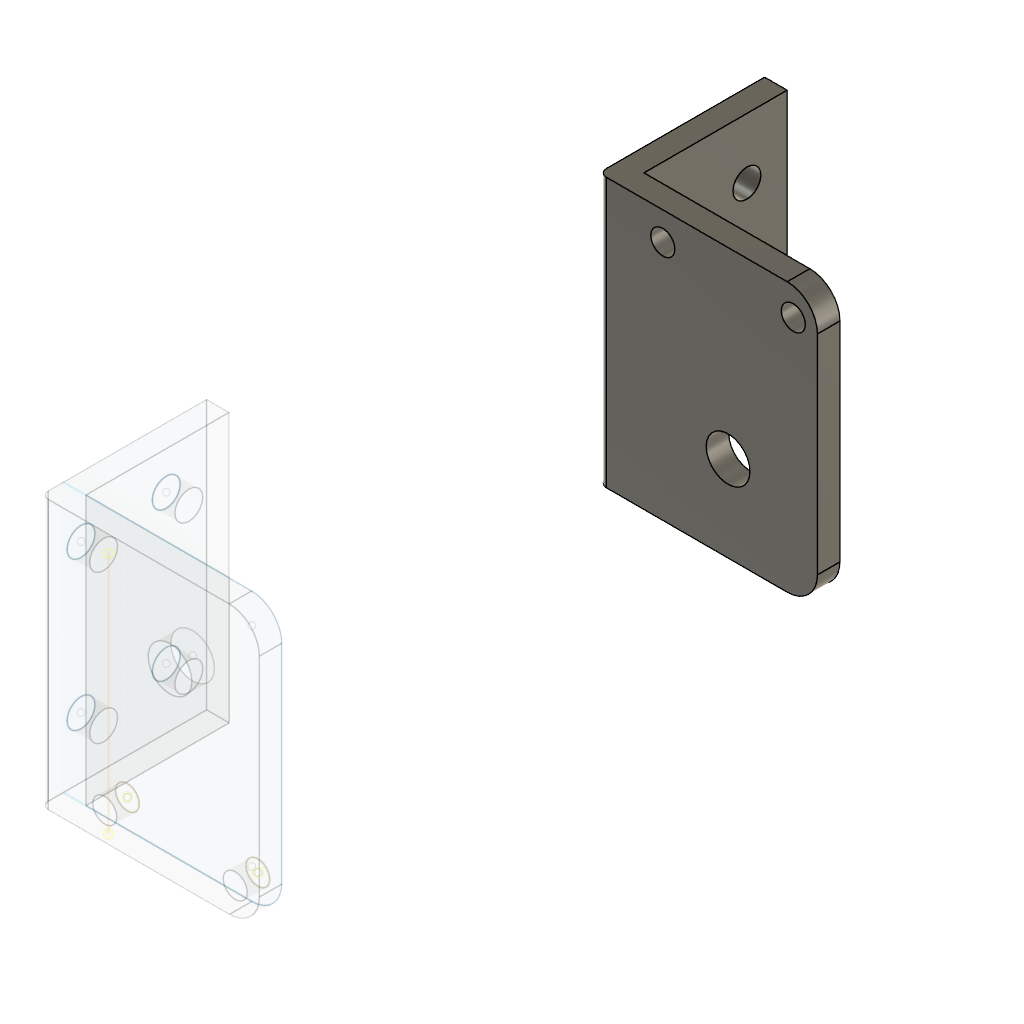
机械车01 (Autodesk Fusion 360 archive; units mm, degrees)
design "motor"
description: STEP AP214
part number: motor
part number: 2026-10-07-12-05-36-152
part number: 2026-10-07-14-24-25-722
Autodesk Fusion 360 part; units mm, degrees
sketch "草图2" plane through (0, -9.65, 0) normal (0, -1, 0) x (1, 0, 0) in component "Component"
  line L0 (-1.9666, 18.47) -> (1.9666, 18.47)
  arc A0 (1.9666, 18.47) -> (-1.9666, 18.47) centre (0, 16.62) ccw
  line L1 (-17.15, 28) -> (7.85, 28)
  line L2 (11.85, 24) -> (11.85, -3.6667)
  line L3 (7.85, -7.6667) -> (-17.15, -7.6667)
  line L4 (-17.15, -7.6667) -> (-17.15, 28)
  circle A1 centre (0, 16.62) radius 2.9
  circle A2 centre (-8.65, -3.95) radius 1.5
  circle A3 centre (8.65, -3.95) radius 1.5
  circle A4 centre (-8.65, -3.95) radius 1.6
  circle A5 centre (8.65, -3.95) radius 1.6
  line L5 (-14.15, 28) -> (-14.15, -7.6667)
  line L6 (-11.15, 22.8) -> (-11.15, -9.4)
  arc A6 (11.85, 24) -> (7.85, 28) centre (7.85, 24) ccw
  arc A7 (7.85, -7.6667) -> (11.85, -3.6667) centre (7.85, -3.6667) ccw
  dimension "d47" = 5.8
  dimension "d48" = 3.2
  dimension "d49" = 3.2
  dimension "d50" = 3
  dimension "d51" = 3
  dimension "d52" = 4
  dimension "d53" = 4
  constraint horizontal L1
  constraint perpendicular L1 L2
  constraint perpendicular L1 L4
  constraint horizontal L3
  constraint concentric A0 A1
  constraint concentric A2 A4
  constraint concentric A3 A5
  constraint coincident L1 L5.start
  constraint coincident L3 L5.end
  constraint perpendicular L3 L5
  constraint tangent L1 A6
  constraint tangent L2 A6
  constraint tangent L2 A7
  constraint tangent L3 A7
  measures "d47" diameter of A1
  measures "d48" diameter of A4
  measures "d49" diameter of A5
  measures "d50" distance of L5 L6
  measures "d51" distance of L4 L5
  measures "d52" radius of A6
  measures "d53" radius of A7
extrude "拉伸4" add sketch "草图2" along normal blind 3 contours L1 L3 L4 L5 | L1 L2 L3 L5 A6 A7 makes body 1 in component "Component"
extrude "拉伸5" add sketch "草图2" against normal blind 19 contours L1 L3 L4 L5 bodies 1 in component "Component"
sketch "草图3" plane through (-17.15, 0, 0) normal (-1, 0, 0) x (0, -1, 0) in component "Component"
  line L0 (-9.35, -7.6667) -> (12.65, -7.6667)
  line L1 (12.65, -7.6667) -> (12.65, 28)
  line L2 (12.65, 28) -> (-9.35, 28)
  line L3 (-9.35, 28) -> (-9.35, -7.6667)
  line L4 (1.65, 28) -> (1.65, -7.6667) construction
  line L5 (-9.35, 10.1667) -> (12.65, 10.1667) construction
  circle A0 centre (-4, 20) radius 1.85
  circle A1 centre (7.3, 20) radius 1.85
  circle A2 centre (-4, 0.3333) radius 1.85
  circle A3 centre (7.3, 0.3333) radius 1.85
  dimension "d58" = 3.7
  constraint midpoint L2 L4.start
  constraint midpoint L0 L4.end
  constraint midpoint L3 L5.start
  constraint midpoint L1 L5.end
  constraint symmetric L4 A0 A1
  constraint symmetric L5 A0 A2
  constraint symmetric L5 A1 A3
  measures "d58" diameter of A0
extrude "拉伸6" cut sketch "草图3" against normal blind 3 contours A0 | A1 | A2 | A3 bodies 1 in component "Component"
fillet "圆角4" radius 1 1 edges at (-17.15, -12.65, 10.1667) on bodies 1 in component "Component"
sketch "草图1" plane through (0, -9.65, 0) normal (0, -1, 0) x (1, 0, 0) in component "支座2"
  line L0 (-14.15, -7.6667) -> (-14.15, 28)
  line L1 (-14.15, 28) -> (7.85, 28)
  arc A0 (11.85, 24) -> (7.85, 28) centre (7.85, 24) ccw
  line L2 (11.85, 24) -> (11.85, -3.6667)
  arc A1 (7.85, -7.6667) -> (11.85, -3.6667) centre (7.85, -3.6667) ccw
  line L3 (7.85, -7.6667) -> (-14.15, -7.6667)
  circle A2 centre (8.65, -3.95) radius 1.6
  circle A3 centre (0, 16.62) radius 2.9
  circle A4 centre (-8.65, -3.95) radius 1.6
  line L4 (-17.15, 28) -> (-14.15, 28)
  line L5 (-14.15, 28) -> (-14.15, -7.6667)
  line L6 (-14.15, -7.6667) -> (-17.15, -7.6667)
  line L7 (-17.15, -7.6667) -> (-17.15, 28)
  line L8 (-17.15, -7.6667) -> (7.85, -7.6667)
  arc A5 (7.85, -7.6667) -> (11.85, -3.6667) centre (7.85, -3.6667) ccw
  line L9 (11.85, 24) -> (11.85, -3.6667)
  arc A6 (11.85, 24) -> (7.85, 28) centre (7.85, 24) ccw
  line L10 (7.85, 28) -> (-14.15, 28)
  line L11 (-14.15, 28) -> (-14.15, -7.6667)
  line L12 (-17.15, 28) -> (-17.15, -7.6667)
  line L13 (-14.15, -7.6667) -> (7.85, -7.6667)
  line L14 (-14.15, 28) -> (-17.15, 28)
  line L15 (11.85, 24) -> (11.85, 28) construction
  line L16 (11.85, 28) -> (7.85, 28) construction
  line L17 (7.85, -7.6667) -> (11.85, -7.6667) construction
  line L18 (11.85, -7.6667) -> (11.85, -3.6667) construction
  line L19 (11.85, 28) -> (-14.15, -7.6667) construction
  line L20 (11.85, -7.6667) -> (-14.15, 28) construction
  line L21 (11.85, 10.1667) -> (-14.15, 10.1667) construction
  circle A7 centre (0, 3.7133) radius 2.9
  circle A8 centre (-8.65, 24.2833) radius 1.6
  circle A9 centre (8.65, 24.2833) radius 1.6
  line L22 (-14.15, -7.6667, 0) -> (-14.15, -7.6667, -19)
  line L23 (-14.15, -7.6667, -19) -> (-17.15, -7.6667, -19)
  line L24 (-17.15, -7.6667, -19) -> (-17.15, -7.6667, 0)
  line L25 (-14.15, 28, -19) -> (-14.15, 28, 0)
  line L26 (-14.15, -7.6667, -19) -> (-14.15, 28, -19)
  point P0 (11.85, -3.6667)
  point P1 (-14.15, -7.6667)
  point P2 (-17.15, -7.6667)
  point P3 (-17.15, -7.6667)
  point P4 (-14.15, 28)
  constraint coincident P3 P2
  constraint coincident A1.start L3.start
  constraint coincident P0 L2.end
  constraint tangent L3 A5
  constraint coincident A0.start L2.start
  constraint tangent A5 L9
  constraint coincident L1.end A0.end
  constraint tangent L9 A6
  constraint coincident P4 L0.end
  constraint coincident P1 L0.start
  constraint coincident L4.start L7.end
  constraint tangent A0 L15
  constraint tangent A6 L16
  constraint tangent A1 L17
  constraint tangent A1 L18
  constraint midpoint L2 L21.start
  constraint midpoint L5 L21.end
  constraint symmetric A2 L21 A9
  constraint symmetric A3 L21 A7
  constraint symmetric A4 L21 A8
  constraint coincident L0.start L3.end
extrude "拉伸1" add sketch "草图1" along normal blind 3 separate body contours L0 L4 L5 L6 L7 L8 L11 L12 L14 | L0 L1 A0 L2 A1 L3 L5 L8 A5 L9 A6 L10 L11 L13 | A2 | A3 | A4 makes body 2 in component "支座2"
sketch "草图2 (2)" plane through (-14.15, 0, 0) normal (1, 0, 0) x (0, 1, 0) in component "支座2"
  circle A0 centre (-7.3, 20) radius 1.85
  circle A1 centre (-7.3, 0.3333) radius 1.85
  circle A2 centre (4, 20) radius 1.85
  circle A3 centre (4, 0.3333) radius 1.85
  line L0 (-9.65, 28) -> (-9.65, -7.6667)
  line L1 (-9.65, -7.6667) -> (9.35, -7.6667)
  line L2 (9.35, -7.6667) -> (9.35, 28)
  line L3 (9.35, 28) -> (-9.65, 28)
  circle A4 centre (4, 0.3333) radius 1.85
  circle A5 centre (-7.3, 0.3333) radius 1.85
  circle A6 centre (4, 20) radius 1.85
  circle A7 centre (-7.3, 20) radius 1.85
  constraint concentric A3 A4
  constraint concentric A1 A5
  constraint concentric A2 A6
  constraint concentric A0 A7
extrude "拉伸2" add sketch "草图2 (2)" against normal blind 3 bodies 2 in component "支座2"
fillet "圆角1" radius 1 1 edges at (-17.15, -12.65, 10.1667) on bodies 2 in component "支座2"
fillet "圆角2" [rolled back] radius 1 in component "Component"
fillet "圆角3" [rolled back] radius 1 in component "Component"
sketch "草图1 (2)" plane through (0, -17.65, 0) normal (0, -1, 0) x (1, 0, 0) in component "Component"
  arc A0 (1.9666, 14.77) -> (1.9666, 18.47) centre (0, 16.62) ccw
  line L0 (1.9666, 18.47) -> (-1.9666, 18.47)
  arc A1 (-1.9666, 18.47) -> (-1.9666, 14.77) centre (0, 16.62) ccw
  line L1 (-1.9666, 14.77) -> (1.9666, 14.77)
  circle A2 centre (0, 16.62) radius 0.95
  line L2 (-14.65, 26.8492) -> (-14.65, -8.725)
  line L3 (-14.65, -8.725) -> (11.8937, -8.725)
  line L4 (11.8937, -8.725) -> (11.8937, 26.8492)
  line L5 (5.8937, 32.8492) -> (-8.65, 32.8492)
  line L6 (-11.65, 32.8492) -> (-11.65, -8.725)
  line L7 (-11.15, 22.8) -> (-11.15, -9.4)
  arc A3 (-8.65, 32.8492) -> (-14.65, 26.8492) centre (-8.65, 26.8492) ccw
  arc A4 (11.8937, 26.8492) -> (5.8937, 32.8492) centre (5.8937, 26.8492) ccw
  circle A5 centre (-8.65, -3.95) radius 1.5
  circle A6 centre (8.65, -3.95) radius 1.5
  circle A7 centre (0, 30.3) radius 1.25
  circle A8 centre (0, 16.62) radius 2.8
  circle A9 centre (-8.65, -3.95) radius 1.6
  circle A10 centre (8.65, -3.95) radius 1.6
  dimension "d33" = 0.5
  dimension "d34" = 3
  dimension "d35" = 6
  dimension "d36" = 5.6
  dimension "d37" = 3.2
  dimension "d38" = 3.2
  constraint vertical L2
  constraint perpendicular L2 L3
  constraint perpendicular L3 L4
  constraint perpendicular L2 L5
  constraint coincident L5 L6.start
  constraint coincident L3 L6.end
  constraint perpendicular L3 L6
  constraint tangent L2 A3
  constraint tangent L5 A3
  constraint tangent L4 A4
  constraint tangent L5 A4
  constraint equal A3 A4
  constraint concentric A0 A8
  constraint concentric A5 A9
  constraint concentric A6 A10
  measures "d33" distance of L6 L7
  measures "d34" distance of L2 L6
  measures "d35" radius of A3
  measures "d36" diameter of A8
  measures "d37" diameter of A9
  measures "d38" diameter of A10
extrude "拉伸1'" [suppressed] in component "Component"
extrude "拉伸2'" [suppressed] in component "Component"
extrude "拉伸3" [suppressed] in component "Component"
fillet "圆角1'" [suppressed] in component "Component"
extrude "拉伸1''" [suppressed]
sketch "草图2 (3)" plane through (-11.15, 0, 0) normal (-1, 0, 0) x (0, -1, 0)
  line L0 (8.55, 27.8) -> (8.55, -9.4)
  line L1 (8.55, -9.4) -> (11.55, -9.4)
  line L2 (11.55, -9.4) -> (11.55, 27.8)
  line L3 (11.55, 27.8) -> (8.55, 27.8)
  line L4 (8.55, 27.8) -> (-10.4031, 27.8)
  line L5 (-10.4031, 27.8) -> (-10.4031, -9.3431)
  line L6 (-10.4031, -9.3431) -> (8.55, -9.4)
  constraint coincident L0.start L3.end
  constraint perpendicular L0 L4
  constraint perpendicular L4 L5
  constraint coincident L0.end L1.start
extrude "拉伸2''" [suppressed]
extrude "拉伸3'" [suppressed]
fillet "圆角1''" [suppressed]
extrude "拉伸4'" [suppressed]
component "Component" placed x (1, 0, 0) y (0, 1, 0) z (0, 0, 1) at (0, 0, 0)
component "支座2" placed x (1, 0, 0) y (0, 1, 0) z (0, 0, 1) at (0, 0, 0)
